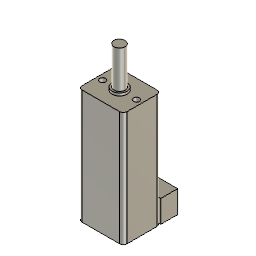
Robot Assembly (Autodesk Fusion 360 archive; units mm, degrees)
design "Motor"
Autodesk Fusion 360 part; units mm, degrees
sketch "Sketch1" plane through (0, 0, 0) normal (0, 0, 1) x (1, 0, 0)
  line L0 (-6, 5) -> (6, 5)
  line L1 (6, 5) -> (6, -5)
  line L2 (6, -5) -> (-6, -5)
  line L3 (-6, -5) -> (-6, 5)
  line L4 (-6, 5) -> (6, -5) construction
  line L5 (6, 5) -> (-6, -5) construction
  dimension "d1" = 12
  dimension "d2" = 10
  constraint horizontal L0
  constraint perpendicular L0 L1
  constraint parallel L0 L2
  constraint parallel L1 L3
  constraint coincident L4 origin
  constraint coincident L5 origin
  measures "d1" distance of L0.start L0.end
  measures "d2" distance of L0.end L1.end
extrude "Extrude1" add sketch "Sketch1" along normal blind 30.5
sketch "Sketch2" plane through (0, 0, 30.5) normal (0, 0, 1) x (-1, 0, 0)
  line L0 (6, 5) -> (-6, 5)
  line L1 (-6, 5) -> (-6, -5)
  line L2 (-6, -5) -> (6, -5)
  line L3 (6, -5) -> (6, 5)
  circle A0 centre (0, 0) radius 2
  dimension "d5" = 4
  constraint coincident A0.centre origin
  measures "d5" diameter of A0
extrude "Extrude2" add sketch "Sketch2" along normal blind 0.7 contours A0
sketch "Sketch3" plane through (0, 0, 31.2) normal (0, 0, 1) x (-1, 0, 0)
  circle A0 centre (0, 0) radius 2
  circle A1 centre (0, 0) radius 1.5
  dimension "d8" = 3
  constraint coincident A0.centre A1.centre
  measures "d8" diameter of A1
extrude "Extrude3" add sketch "Sketch3" along normal blind 10 contours A1
sketch "Sketch4" plane through (0, 0, 30.5) normal (0, 0, 1) x (-1, 0, 0)
  circle A0 centre (0, 0) radius 2
  line L0 (6, 5) -> (-6, 5)
  line L1 (-6, 5) -> (-6, -5)
  line L2 (-6, -5) -> (6, -5)
  line L3 (6, -5) -> (6, 5)
  circle A1 centre (0, 0) radius 1.5
  line L4 (6, -5) -> (-6, 5) construction
  line L5 (-6, -5) -> (6, 5) construction
  circle A2 centre (4.5, 0) radius 0.8
  circle A3 centre (-4.5, 0) radius 0.8
  point P0 (6, -5)
  point P1 (-6, 5)
  point P2 (-6, -5)
  point P3 (6, 5)
  dimension "d11" = 9
  dimension "d12" = 1.5
  dimension "d13" = 1.6
  dimension "d14" = 1.6
  constraint coincident P0 L2.end
  constraint coincident P1 L0.end
  constraint coincident P2 L1.end
  constraint coincident P3 L0.start
  measures "d11" distance of A2.centre A3.centre
  measures "d12" distance of L3 A2.centre
  measures "d13" diameter of A2
  measures "d14" diameter of A3
extrude "Extrude4" cut sketch "Sketch4" against normal blind 2 contours A2 | A3
fillet "Fillet1" radius 1 4 edges at (-6, 5, 15.25) (6, 5, 15.25) (-6, -5, 15.25) (6, -5, 15.25)
sketch "Sketch5" plane through (0, 5, 0) normal (0, 1, 0) x (-1, 0, 0)
  line L0 (-5, 30.5) -> (-5, 0)
  line L1 (-5, 0) -> (5, 0)
  line L2 (5, 0) -> (5, 30.5)
  line L3 (5, 30.5) -> (-5, 30.5)
  line L4 (-6, 0) -> (6, 0)
  line L5 (6, 0) -> (6, 6)
  line L6 (6, 6) -> (-6, 6)
  line L7 (-6, 6) -> (-6, 0)
  line L8 (-6, 30.5) -> (-6, 0)
  dimension "d19" = 12
  dimension "d20" = 6
  constraint horizontal L4
  constraint vertical L5
  constraint horizontal L6
  constraint vertical L7
  constraint collinear L1 L4
  constraint collinear L7 L8
  measures "d19" distance of L4.start L4.end
  measures "d20" distance of L4.start L6.end
extrude "Extrude5" add sketch "Sketch5" along normal blind 4.5 contours L0 L1 L2 L4 L6 | L0 L4 L6 L7 L8 | L2 L4 L5 L6

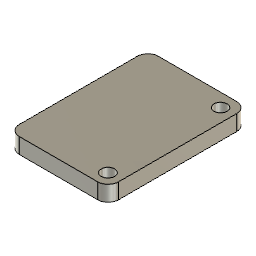
design "Motor Controller"
Autodesk Fusion 360 part; units mm, degrees
sketch "Sketch1" plane through (0, 0, 0) normal (0, 0, 1) x (1, 0, 0)
  line L0 (-9.525, 13.335) -> (9.525, 13.335)
  line L1 (9.525, 13.335) -> (9.525, -13.335)
  line L2 (9.525, -13.335) -> (-9.525, -13.335)
  line L3 (-9.525, -13.335) -> (-9.525, 13.335)
  line L4 (-9.525, 13.335) -> (9.525, -13.335) construction
  line L5 (9.525, 13.335) -> (-9.525, -13.335) construction
  circle A0 centre (6.985, 10.755) radius 1.25
  circle A1 centre (6.985, -10.835) radius 1.27
  dimension "d1" = 19.05
  dimension "d2" = 26.67
  dimension "d3" = 16.51
  dimension "d4" = 16.51
  dimension "d5" = 21.59
  dimension "d6" = 2.5
  dimension "d7" = 2.54
  dimension "d8" = 2.5
  constraint horizontal L0
  constraint perpendicular L0 L1
  constraint parallel L0 L2
  constraint parallel L1 L3
  constraint coincident L4 origin
  constraint coincident L5 origin
  measures "d1" distance of L1.end L2.end
  measures "d2" distance of L0.end L1.end
  measures "d3" distance of L3 A1.centre
  measures "d4" distance of L3 A0.centre
  measures "d5" distance of A0.centre A1.centre
  measures "d6" diameter of A0
  measures "d7" diameter of A1
  measures "d8" distance of L2 A1.centre
extrude "Extrude1" add sketch "Sketch1" along normal blind 3
fillet "Fillet1" radius 2 4 edges at (9.525, -13.335, 1.5) (-9.525, -13.335, 1.5) (9.525, 13.335, 1.5) (-9.525, 13.335, 1.5)
